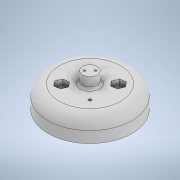
# Autodesk Inventor part: suport_craniiue
Saved by Autodesk Inventor 2022.6 (Build 266554000, 554)
## iProperties
Created: 2026-03-13
Part Number: suport_craniiue
Material: Generic
Document SubType Name: Modeling
Designer: Dragos Macovei
Density: 1 g/cm^3
Appearance: Default
Author: Dragos Macovei
Autodesk Inventor part; units mm, degrees
ref_plane "YZ Plane" through (0, 0, 0) normal (1, 0, 0) x (0, 1, 0)
ref_plane "XZ Plane" through (0, 0, 0) normal (0, 1, 0) x (-1, 0, 0)
ref_plane "XY Plane" through (0, 0, 0) normal (0, 0, 1) x (1, 0, 0)
sketch "Sketch1" plane through (0, 0, 0) normal (0, 1, 0) x (-1, 0, 0)
  circle A0 centre (0, 0) radius 6.5
  dimension "d0" = 13
  constraints: 1 centre point, 1 coincident
  measures "d0" diameter of A0
extrude "Extrusion1" add sketch "Sketch1" along normal blind 10
sketch "Sketch2" plane through (0, 10, 0) normal (0, 1, 0) x (1, 0, 0)
  circle A0 centre (-2.4749, -2.4749) radius 1
  circle A1 centre (2.4749, 2.4749) radius 1
  circle A2 centre (0, 0) radius 6.5 projected
  line L0 (0, 0) -> (31.8198, 31.8198)
  line L1 (0, 0) -> (45, 0) construction
  line L2 (31.8198, 31.8198) -> (-7.4227, -7.4227)
  dimension "d3" = 2
  dimension "d4" = 2
  dimension "d5" = 2
  dimension "d6" = 2
  dimension "d7" = 45
  dimension "d8" = 45
  constraints: 6 end point, 3 point on line, 2 centre point, 1 equal length, 1 horizontal
  measures "d3" diameter of A0
  measures "d4" diameter of A1
  measures "d7" distance of L0.start L0.end
  measures "d8" angle of L1 L0
extrude "Extrusion2" cut sketch "Sketch2" against normal through all contours A0 L2 | L2 A0 | L0 A1 | A1 L0
sketch "Sketch3" plane through (0, 0, 0) normal (0, -1, 0) x (1, 0, 0)
  circle A0 centre (0, 0) radius 37.5
  dimension "d11" = 75
  constraints: 1 centre point, 1 coincident
  measures "d11" diameter of A0
extrude "Extrusion3" add sketch "Sketch3" along normal blind 20
fillet "Fillet1" radius 10 1 edges at (-37.5, 0, 0)
sketch "Sketch4" plane through (0, -20, 0) normal (0, -1, 0) x (1, 0, 0)
  point P0 (0, 0)
sketch "Sketch5" plane through (0, 10, 0) normal (0, 1, 0) x (1, 0, 0)
  circle A0 centre (2.4749, 2.4749) radius 1 projected
  circle A1 centre (-2.4749, -2.4749) radius 1 projected
  circle A2 centre (0, 0) radius 6.5 projected
extrude "Extrusion4" cut sketch "Sketch5" against normal through all contours A0 | A1
sketch "Sketch6" plane through (0, 0, 0) normal (0, 1, 0) x (1, 0, 0)
  circle A0 centre (0, 0) radius 6.5 projected
  circle A1 centre (0, 0) radius 27.5 projected
  line L0 (0, 0) -> (17.7439, -17.7439)
  line L1 (0, 0) -> (25.0936, 0) construction
  line L2 (17.7439, -17.7439) -> (-20.5443, 20.5443)
  circle A2 centre (-12.7279, 12.7279) radius 1.25
  circle A3 centre (12.7279, -12.7279) radius 1.25
  dimension "d17" = 45
  dimension "d18" = 2.5
  dimension "d19" = 2.5
  dimension "d20" = 36
  dimension "d21" = 18
  constraints: 6 end point, 3 point on line, 2 centre point, 2 coincident, 1 equal length, 1 horizontal
  measures "d17" angle of L0 L1
  measures "d18" diameter of A2
  measures "d19" diameter of A3
  measures "d20" distance of A3.centre A2.centre
  measures "d21" distance of point (0, 0) A2.centre
extrude "Extrusion5" cut sketch "Sketch6" against normal through all contours A3 L0 | L0 A3 | A2 L2 | L2 A2
sketch "Sketch7" plane through (0, -20, 0) normal (0, -1, 0) x (1, 0, 0)
  circle A0 centre (12.7279, 12.7279) radius 1.25 projected
  circle A1 centre (-12.7279, -12.7279) radius 1.25 projected
  circle A2 centre (-2.4749, 2.4749) radius 1 projected
  circle A3 centre (2.4749, -2.4749) radius 1 projected
  circle A4 centre (0, 0) radius 37.5 projected
  circle A5 centre (-12.7279, -12.7279) radius 5
  circle A6 centre (12.7279, 12.7279) radius 5
  circle A7 centre (0, 0) radius 7.5
  dimension "d24" = 10
  dimension "d25" = 10
  dimension "d26" = 15
  constraints: 3 centre point, 3 coincident
  measures "d24" diameter of A5
  measures "d25" diameter of A6
  measures "d26" diameter of A7
extrude "Extrusion6" cut sketch "Sketch7" against normal blind 5 contours A5 | A6 | A7
sketch "Sketch9" plane through (0, 0, 0) normal (0, 1, 0) x (1, 0, 0)
  line L0 (3.4234, 2.7434) -> (-11.0562, -11.7362)
  line L1 (3.4234, 2.7434) -> (23.9006, 2.7434) construction
  line L2 (-11.0562, -11.7362) -> (25.7755, 25.0956)
  line L3 (-15.8025, -8.7011) -> (-10.3151, -7.9212)
  line L4 (-10.3151, -7.9212) -> (-6.896, -12.2835)
  line L5 (-6.896, -12.2835) -> (-8.9643, -17.4257)
  line L6 (-8.9643, -17.4257) -> (-14.4517, -18.2056)
  line L7 (-14.4517, -18.2056) -> (-17.8708, -13.8433)
  line L8 (-17.8708, -13.8433) -> (-15.8025, -8.7011)
  line L9 (9.5558, 16.6766) -> (15.0242, 17.58)
  line L10 (15.0242, 17.58) -> (18.5409, 13.2959)
  line L11 (18.5409, 13.2959) -> (16.5891, 8.1084)
  line L12 (16.5891, 8.1084) -> (11.1206, 7.205)
  line L13 (11.1206, 7.205) -> (7.604, 11.489)
  line L14 (7.604, 11.489) -> (9.5558, 16.6766)
  circle A0 centre (2.4749, 2.4749) radius 1 projected
  circle A1 centre (-2.4749, -2.4749) radius 1 projected
  circle A2 centre (0, 0) radius 6.5 projected
  circle A3 centre (0, 0) radius 6.5 projected
  point P0 (-12.3834, -13.0634)
  point P1 (13.0724, 12.3925)
  point P2 (12.29, 17.1283)
  dimension "d39" = 135
  dimension "d40" = 9.6
  dimension "d41" = 9.6
  dimension "d43" = 36
  dimension "d44" = 18
  constraints: 30 end point, 3 point on line, 1 equal length, 1 horizontal, 1 midpoint, 26 other
  measures "d39" angle of L0 L1
  measures "d40" distance from line of L12 point (12.29, 17.128)
  measures "d41" distance between parallel lines of L6 L3
  measures "d43" distance of point (-12.383, -13.063) point (13.072, 12.392)
  measures "d44" distance of A3.centre point (-12.383, -13.063)
extrude "Extrusion7" cut sketch "Sketch9" against normal blind 8 contours L13 L14 L9 L10 L2 | L2 L10 L11 L12 L13 | L4 L5 L6 L7 L8 L3
sketch "Sketch10" plane through (0, -8, 0) normal (0, 1, 0) x (1, 0, 0)
  line L0 (-17.8708, -13.8433) -> (-15.8025, -8.7011) projected
  line L1 (-14.4517, -18.2056) -> (-17.8708, -13.8433) projected
  line L2 (-8.9643, -17.4257) -> (-14.4517, -18.2056) projected
  line L3 (-6.896, -12.2835) -> (-8.9643, -17.4257) projected
  line L4 (-10.3151, -7.9212) -> (-6.896, -12.2835) projected
  line L5 (-15.8025, -8.7011) -> (-10.3151, -7.9212) projected
  line L6 (18.5409, 13.2959) -> (16.5891, 8.1084) projected
  line L7 (15.0242, 17.58) -> (18.5409, 13.2959) projected
  line L8 (9.5558, 16.6766) -> (15.0242, 17.58) projected
  line L9 (7.604, 11.489) -> (9.5558, 16.6766) projected
  line L10 (11.1206, 7.205) -> (7.604, 11.489) projected
  line L11 (16.5891, 8.1084) -> (11.1206, 7.205) projected
  circle A0 centre (-12.3834, -13.0634) radius 3.25
  circle A1 centre (13.0724, 12.3925) radius 3.25
  point P0 (0, 0)
  dimension "d47" = 6.5
  dimension "d48" = 6.5
  constraints: 2 centre point, 2 coincident
  measures "d47" diameter of A0
  measures "d48" diameter of A1
extrude "Extrusion8" cut sketch "Sketch10" against normal through all contours A0 | A1
fillet "Fillet2" radius 2 1 edges at (6.5, 0, 0)
body "Solid1"
